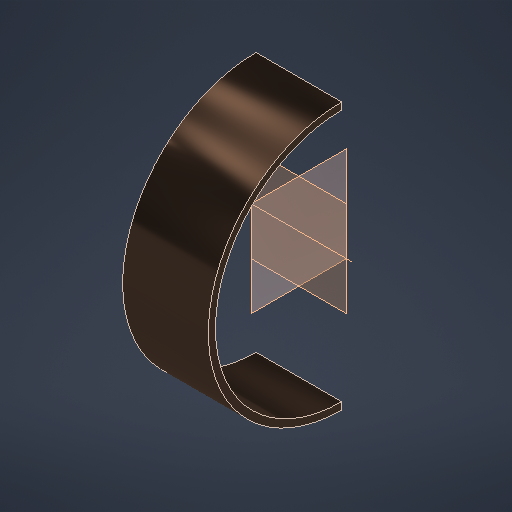
# Autodesk Inventor part: Rod_Shell_Upper
Saved by Autodesk Inventor 2027.1 (Build 311270010, 270A)
## iProperties
Created: 2026-10-17
Part Number: Rod_Shell_Upper
Material: Bronze
Document SubType Name: Modeling
Designer: kashyap
Density: 8.47 g/cm^3
Appearance: Bronze - Polished
Mass: 19.5979 g
Surface Area: 33.9616 cm^2
Volume: 2.3138 cm^3
Material_Status: Assumed for this reconstruction
Author: kashyap
Autodesk Inventor part; units mm, degrees
derived "V6_Engine_Master.ipt"
ref_plane "Shell_Mid_Plane" through (0, 0, 0) normal (1, 0, 0) x (0, 1, 0)
ref_plane "Shell_Split_Plane" through (0, 0, 0) normal (0, 0, 1) x (1, 0, 0)
sketch "SK_Shell" plane through (0, 0, 0) normal (1, 0, 0) x (0, 1, 0)
  circle A0 centre (0, 0) radius 28.028
  circle A1 centre (0, 0) radius 26.528
  dimension "d21" = 56.056
  dimension "d22" = 53.056
  constraints: 2 centre point
  measures "d21" diameter of A0
  measures "d22" diameter of A1
extrude "Shell_Ring" add sketch "SK_Shell" along normal mid plane 18
sketch "SK_Half_Cut" plane through (0, 0, 0) normal (1, 0, 0) x (0, 1, 0)
  line L0 (-40, 0) -> (40, 0)
  line L1 (40, 0) -> (40, -40)
  line L2 (40, -40) -> (-40, -40)
  line L3 (-40, -40) -> (-40, 0)
  constraints: 8 end point, 2 parallel, 1 horizontal, 1 perpendicular
extrude "Half_Cut" cut sketch "SK_Half_Cut" along normal mid plane 20
equation "\"d21\" = Rod_Shell_OD"
equation "\"d22\" = Rod_Shell_ID"
equation "\"d23\" = Rod_Shell_Width"
equation "\"Rod_Shell_OD\" = 56.056"
equation "\"Rod_Shell_ID\" = 53.056"
equation "\"Rod_Shell_Width\" = 18"
body "Solid1"
